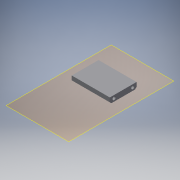
# Autodesk Inventor part: pieza soldada a vertical
Saved by Autodesk Inventor 2017 (Build 210142000, 142)
## iProperties
Part Number: pieza soldada a vertical
Material: Genérico
Document SubType Name: Modeling
Designer: HP Pav
Density: 1 g/cm^3
Appearance: Valor por defecto
Author: HP Pav
Autodesk Inventor part; units mm, degrees
ref_plane "YZ Plane" through (0, 0, 0) normal (1, 0, 0) x (0, 1, 0)
ref_plane "XZ Plane" through (0, 0, 0) normal (0, 1, 0) x (-1, 0, 0)
ref_plane "XY Plane" through (0, 0, 0) normal (0, 0, 1) x (1, 0, 0)
ref_plane "Plano de trabajo1" through (0, 0, 0) normal (0, 0, 1) x (1, 0, 0)
sketch "Boceto1" plane through (0, 0, 0) normal (0, 0, 1) x (1, 0, 0)
  line L0 (0, 196.5) -> (149, 196.5) projected
  line L1 (0, 0) -> (0, 196.5) projected
  line L2 (149, 0) -> (149, 196.5) projected
  line L3 (25.3, 196.5) -> (124.8, 196.5)
  line L4 (124.8, 196.5) -> (124.8, 126.5)
  line L5 (124.8, 126.5) -> (25.3, 126.5)
  line L6 (25.3, 126.5) -> (25.3, 196.5)
  dimension "d0" = 70
  dimension "d3" = 99.5
  dimension "d4" = 25.3
  constraints: 8 end point, 2 parallel, 1 horizontal, 1 perpendicular, 1 point on line
  measures "d0" distance of L5.end L3.start
  measures "d3" distance between parallel lines of L4 L6
  measures "d4" distance between parallel lines of L1 L6
extrude "Extrusión1" add sketch "Boceto1" along normal blind 15
hole "Agujero1" at (25.3, 186.7, 7.5) direction (1, 0, 0) diameter 8 depth 8 tip angle 118
hole "Agujero2" at (25.3, 137.8, 7.5) direction (1, 0, 0) diameter 8 depth 8 tip angle 118
hole "Agujero3" at (124.8, 186.7, 7.5) direction (-1, 0, 0) diameter 8 depth 8 tip angle 118
hole "Agujero4" at (124.8, 137.8, 7.5) direction (-1, 0, 0) diameter 8 depth 8 tip angle 118
chamfer "Chaflán1" distance 4 angle 45 1 edges at (75.05, 196.5, 0)
chamfer "Chaflán2" distance 4 angle 45 1 edges at (75.05, 126.5, 0)
